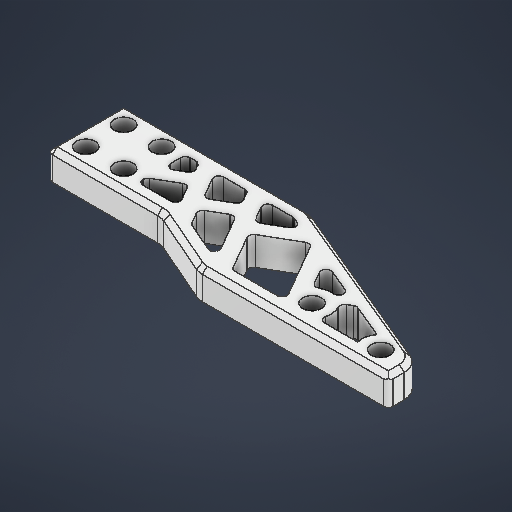
# Autodesk Inventor part: Tongs_l
Saved by Autodesk Inventor 2026.2 (Build 302298010, 298A)
## iProperties
Created: 2026-05-08
Part Number: Tongs_l
Material: ABS 플라스틱
Document SubType Name: Modeling
Designer: work
Density: 1.06 g/cm^3
Appearance: 매끄러움 - 흰색
Author: work
Autodesk Inventor part; units mm, degrees
ref_plane "YZ Plane" through (0, 0, 0) normal (1, 0, 0) x (0, 1, 0)
ref_plane "XZ Plane" through (0, 0, 0) normal (0, 1, 0) x (-1, 0, 0)
sketch "스케치1" plane through (0, 0, 0) normal (0, 1, 0) x (-1, 0, 0)
  line L0 (-4, 4) -> (4, 4) construction
  line L1 (4, 4) -> (4, -4) construction
  line L2 (4, -4) -> (-4, -4) construction
  line L3 (-4, -4) -> (-4, 4) construction
  line L4 (-4, 4) -> (4, -4) construction
  line L5 (4, 4) -> (-4, -4) construction
  circle A0 centre (4, 4) radius 2
  circle A1 centre (4, -4) radius 2
  circle A2 centre (-4, -4) radius 2
  circle A3 centre (-4, 4) radius 2
  line L6 (-8, 8) -> (8, 8)
  line L7 (8, 8) -> (8, -8)
  line L8 (8, -8) -> (-8, -8)
  line L9 (-8, -8) -> (-8, 8)
  line L10 (-8, 8) -> (8, -8) construction
  line L11 (8, 8) -> (-8, -8) construction
  line L12 (-8, 8) -> (-16, 8)
  line L13 (-16, 8) -> (-29.7477, 14)
  line L14 (-29.7477, 14) -> (-69.7477, 14)
  line L15 (-69.7477, 14) -> (-69.7477, 8)
  line L16 (-69.7477, 8) -> (-31.3982, -8)
  line L17 (-31.3982, -8) -> (-8, -8)
  line L18 (-8, -5) -> (-30.7974, -5)
  line L19 (-30.7974, -5) -> (-66.7477, 9.999)
  line L20 (-66.7477, 9.999) -> (-66.7477, 11)
  line L21 (-66.7477, 11) -> (-30.3739, 11)
  line L22 (-30.3739, 11) -> (-16.6261, 5)
  line L23 (-16.6261, 5) -> (-8, 5)
  line L24 (-48.5608, 11) -> (-42.0285, -0.3142)
  line L25 (-45.0967, 11) -> (-37.4652, -2.2181)
  line L26 (-30.3739, 11) -> (-21.1363, -5)
  line L27 (-33.838, 11) -> (-24.6004, -5)
  line L28 (-16.6261, 5) -> (-10.8526, -5)
  line L29 (-21.2571, 7.0211) -> (-14.3167, -5)
  line L30 (-37.4652, -2.2181) -> (-29.0212, 2.6571)
  line L31 (-27.5212, 0.059) -> (-33.9822, -3.6713)
  line L32 (-13.7394, 0) -> (-8, 3.3136)
  line L33 (-12.2394, -2.5981) -> (-8, -0.1505)
  line L34 (-17.7869, 1.0106) -> (-22.9016, -1.9424)
  line L35 (-24.4016, 0.6557) -> (-19.2869, 3.6086)
  line L36 (-46.0285, 6.614) -> (-51.3166, 3.5609)
  line L37 (-47.0285, 8.346) -> (-53.6386, 4.5297)
  point P0 (0, 0)
  point P1 (-30.7517, -1.8061)
  dimension "d0" = 8
  dimension "d1" = 8
  dimension "d2" = 4
  dimension "d3" = 4
  dimension "d4" = 4
  dimension "d5" = 4
  dimension "d6" = 4
  dimension "d7" = 8
  dimension "d8" = 15
  dimension "d9" = 40
  dimension "d10" = 6
  dimension "d11" = 38.3496
  dimension "d12" = 3
  dimension "d13" = 3
  dimension "d14" = 3
  dimension "d15" = 3
  dimension "d16" = 120
  dimension "d17" = 3
  dimension "d18" = 3
  dimension "d19" = 2
  dimension "d20" = 8
  dimension "d21" = 3
  constraints: 76 end point, 24 point on line, 19 parallel, 8 midpoint, 6 perpendicular, 4 centre point, 4 coincident, 3 horizontal, 5 other
  measures "d0" distance of L1.end L2.end
  measures "d1" distance of L0.end L1.end
  measures "d2" diameter of A0
  measures "d3" diameter of A1
  measures "d4" diameter of A2
  measures "d5" diameter of A3
  measures "d6" distance between parallel lines of L7 L1
  measures "d7" distance of L6.start L12.end
  measures "d8" distance of L12.end L13.end
  measures "d9" distance of L13.end L14.end
  measures "d10" distance of L14.end L15.end
  measures "d11" horizontal distance of L15.end L16.end
  measures "d12" distance between parallel lines of L13 L22
  measures "d13" distance between parallel lines of L24 L25
  measures "d14" distance between parallel lines of L27 L26
  measures "d15" distance between parallel lines of L29 L28
  measures "d16" angle of L21 L27
  measures "d17" distance between parallel lines of L34 L35
  measures "d18" distance from line of L30 point (-30.752, -1.806)
  measures "d19" distance between parallel lines of L37 L36
  measures "d20" distance from line of L24.end L36
  measures "d21" distance between parallel lines of L33 L32
extrude "돌출1" add sketch "스케치1" along normal blind 6 contours L6 L7 L8 L9 | L9 L23 L22 L21 L20 L19 L18 L17 L16 L15 L14 L13 L12 | L9 L33 L28 L32 | L28 L18 L29 L22 | L26 L18 L27 L21 | L29 L34 L26 L35 | L25 L19 L24 L21 | L27 L31 L19 L30 | L24 L36 L19 L37
sketch "스케치2" plane through (0, 6, 0) normal (0, 1, 0) x (1, 0, 0)
  line L0 (16, -8) -> (29.7477, -14) projected
  line L1 (29.7477, -14) -> (69.7477, -14) projected
  line L2 (69.7477, -14) -> (69.7477, -8) projected
  line L3 (69.7477, -8) -> (31.3982, 8) projected
  line L4 (31.3982, 8) -> (-8, 8) projected
  line L5 (-8, 8) -> (-8, -8) projected
  line L6 (-8, -8) -> (16, -8) projected
  line L7 (27.5212, -0.059) -> (24.6004, 5) projected
  line L8 (24.6004, 5) -> (30.7974, 5) projected
  line L9 (30.7974, 5) -> (33.9822, 3.6713) projected
  line L10 (33.9822, 3.6713) -> (27.5212, -0.059) projected
  line L11 (12.2394, 2.5981) -> (8, 0.1505) projected
  line L12 (8, 0.1505) -> (8, 5) projected
  line L13 (8, 5) -> (10.8526, 5) projected
  line L14 (10.8526, 5) -> (12.2394, 2.5981) projected
  line L15 (17.7869, -1.0106) -> (14.3167, 5) projected
  line L16 (14.3167, 5) -> (21.1363, 5) projected
  line L17 (21.1363, 5) -> (22.9016, 1.9424) projected
  line L18 (22.9016, 1.9424) -> (17.7869, -1.0106) projected
  line L19 (46.0285, -6.614) -> (42.0285, 0.3142) projected
  line L20 (42.0285, 0.3142) -> (51.3166, -3.5609) projected
  line L21 (51.3166, -3.5609) -> (46.0285, -6.614) projected
  line L22 (13.7394, 0) -> (16.6261, -5) projected
  line L23 (16.6261, -5) -> (8, -5) projected
  line L24 (8, -5) -> (8, -3.3136) projected
  line L25 (8, -3.3136) -> (13.7394, 0) projected
  line L26 (19.2869, -3.6086) -> (24.4016, -0.6557) projected
  line L27 (24.4016, -0.6557) -> (30.3739, -11) projected
  line L28 (30.3739, -11) -> (21.2571, -7.0211) projected
  line L29 (21.2571, -7.0211) -> (19.2869, -3.6086) projected
  line L30 (29.0212, -2.6571) -> (37.4652, 2.2181) projected
  line L31 (37.4652, 2.2181) -> (45.0967, -11) projected
  line L32 (45.0967, -11) -> (33.838, -11) projected
  line L33 (33.838, -11) -> (29.0212, -2.6571) projected
  circle A0 centre (4, -4) radius 2 projected
  circle A1 centre (4, 4) radius 2 projected
  circle A2 centre (-4, 4) radius 2 projected
  circle A3 centre (-4, -4) radius 2 projected
  line L34 (47.0285, -8.346) -> (53.6386, -4.5297) projected
  line L35 (53.6386, -4.5297) -> (66.7477, -9.999) projected
  line L36 (66.7477, -9.999) -> (66.7477, -11) projected
  line L37 (66.7477, -11) -> (48.5608, -11) projected
  line L38 (48.5608, -11) -> (47.0285, -8.346) projected
  point P0 (0, 0)
  constraints: 4 coincident
hole "구멍1" at (-4, 6, 4) at (4, 6, 4) at (4, 6, -4) at (-4, 6, -4) direction (0, -1, 0) diameter 4 end through all counterbore diameter 6.2 counterbore depth 3
fillet "모깎기1" radius 1 30 edges at (8, 3, -5) (8, 3, -0.1505) (10.8526, 3, -5) (12.2394, 3, -2.5981) (13.7394, 3, 0) (8, 3, 3.3136) (8, 3, 5) (16.6261, 3, 5) (17.7869, 3, 1.0106) (33.9822, 3, -3.6713) (30.7974, 3, -5) (27.5212, 3, 0.059) (24.6004, 3, -5) (22.9016, 3, -1.9424) (21.1363, 3, -5) (42.0285, 3, -0.3142) (46.0285, 3, 6.614) (53.6386, 3, 4.5297) (66.7477, 3, 9.999) (51.3166, 3, 3.5609) (24.4016, 3, 0.6557) (30.3739, 3, 11) (21.2571, 3, 7.0211) (45.0967, 3, 11) (37.4652, 3, -2.2181) (33.838, 3, 11) (29.0212, 3, 2.6571) (48.5608, 3, 11) (66.7477, 3, 11) (47.0285, 3, 8.346)
fillet "모깎기2" radius 4 4 edges at (16, 3, 8) (29.7477, 3, 14) (69.7477, 3, 8) (31.3982, 3, -8)
fillet "모깎기3" radius 1 3 edges at (-8, 3, 8) (-8, 3, -8) (69.7477, 3, 14)
chamfer "모따기1" distance 1 angle 45 14 edges at (29.7653, 0, 13.9156) (49.6652, 0, 14) (69.4548, 0, 13.7071) (69.7477, 0, 11.8327) (69.0764, 0, 8.4473) (49.7126, 0, -0.3589) (31.3826, 0, -7.9221) (11.7986, 0, -8) (-7.7071, 0, -7.7071) (-8, 0, 0) (-7.7071, 0, 7.7071) (4.0826, 0, 8) (15.9824, 0, 8.0844) (22.8739, 0, 11)
ref_plane "작업 평면1" through (0, 0, 0) normal (0, -1, 0) x (1, 0, 0)
mirror "미러1" about plane through (0, 0, 0) normal (0, -1, 0) of "돌출1", "구멍1"
sketch "스케치3" plane through (-8, 0, 8) normal (0, 0, 1) x (1, 0, 0)
  line L0 (39.3982, 0) -> (0, 0) projected
  line L1 (0, 0) -> (80.7132, 0)
  line L2 (80.7132, 0) -> (80.7132, 23.1033)
  line L3 (80.7132, 23.1033) -> (0, 23.1033)
  line L4 (0, 23.1033) -> (0, 0)
  point P0 (8, 0)
  constraints: 8 end point, 2 parallel, 1 horizontal, 1 perpendicular
extrude "돌출2" cut sketch "스케치3" along normal through all both and the other way through all
fillet "모깎기4" radius 1 34 edges at (66.7477, -3, 9.999) (53.6386, -3, 4.5297) (66.7477, -3, 11) (37.4652, -3, -2.2181) (46.0285, -3, 6.614) (19.2869, -3, 3.6086) (22.9016, -3, -1.9424) (30.7974, -3, -5) (29.0212, -3, 2.6571) (8, -3, -0.1505) (8, -3, 3.3136) (51.3166, -3, 3.5609) (47.0285, -3, 8.346) (48.5608, -3, 11) (45.0967, -3, 11) (33.838, -3, 11) (30.3739, -3, 11) (21.2571, -3, 7.0211) (42.0285, -3, -0.3142) (33.9822, -3, -3.6713) (24.4016, -3, 0.6557) (21.1363, -3, -5) (24.6004, -3, -5) (27.5212, -3, 0.059) (17.7869, -3, 1.0106) (14.3167, -3, -5) (8, -3, 5) (16.6261, -3, 5) (13.7394, -3, 0) (12.2394, -3, -2.5981) (10.8526, -3, -5) (8, -3, -5) (-8, -3, -8) (-8, -3, 8)
fillet "모깎기5" radius 4 4 edges at (29.7477, -3, 14) (31.3982, -3, -8) (16, -3, 8) (69.7477, -3, 8)
chamfer "모따기2" distance 1 angle 45 12 edges at (49.7126, 0, -0.3589) (31.3826, 0, -7.9221) (11.7986, 0, -8) (-7.7071, 0, -7.7071) (-8, 0, 0) (-7.7071, 0, 7.7071) (4.0826, 0, 8) (15.9824, 0, 8.0844) (22.8739, 0, 11) (29.7653, 0, 13.9156) (50.1652, 0, 14) (69.7477, 0, 12.3327)
sketch "스케치4" plane through (-8, -6, -7) normal (0, -1, 0) x (1, 0, 0)
  arc A0 (38.5972, -1) -> (40.1374, -0.6916) centre (38.5972, 3) ccw projected
  line L0 (75.2879, 13.9737) -> (40.1374, -0.6916) projected
  line L1 (77.7477, 21) -> (77.7477, 17.6653) projected
  line L2 (38.5826, 21) -> (77.7477, 21) projected
  arc A1 (38.5826, 21) -> (36.9826, 20.6661) centre (38.5826, 17) ccw projected
  line L3 (24.7652, 15.3339) -> (36.9826, 20.6661) projected
  arc A2 (23.1652, 15) -> (24.7652, 15.3339) centre (23.1652, 19) ccw projected
  line L4 (1, 15) -> (23.1652, 15) projected
  arc A3 (1, 15) -> (0, 14) centre (1, 14) ccw projected
  line L5 (0, 0) -> (0, 14) projected
  arc A4 (0, 0) -> (1, -1) centre (1, 0) ccw projected
  line L6 (38.5972, -1) -> (1, -1) projected
  circle A5 centre (4, 3) radius 3.1 projected
  circle A6 centre (4, 11) radius 3.1 projected
  circle A7 centre (12, 11) radius 3.1 projected
  circle A8 centre (12, 3) radius 3.1 projected
  line L7 (40.2317, 4.3394) -> (36.3872, 6.559) projected
  arc A9 (40.1168, 2.5504) -> (40.2317, 4.3394) centre (39.7317, 3.4733) ccw projected
  line L8 (38.9822, 2.0771) -> (40.1168, 2.5504) projected
  arc A10 (38.5972, 2) -> (38.9822, 2.0771) centre (38.5972, 3) ccw projected
  line L9 (34.3324, 2) -> (38.5972, 2) projected
  arc A11 (33.4664, 3.5) -> (34.3324, 2) centre (34.3324, 3) ccw projected
  line L10 (35.0212, 6.193) -> (33.4664, 3.5) projected
  arc A12 (36.3872, 6.559) -> (35.0212, 6.193) centre (35.8872, 5.693) ccw projected
  line L11 (16, 5.1175) -> (16, 3) projected
  arc A13 (17.5, 5.9835) -> (16, 5.1175) centre (17, 5.1175) ccw projected
  line L12 (19.3734, 4.9019) -> (17.5, 5.9835) projected
  arc A14 (19.7394, 3.5359) -> (19.3734, 4.9019) centre (18.8734, 4.0359) ccw projected
  line L13 (19.1413, 2.5) -> (19.7394, 3.5359) projected
  arc A15 (18.2753, 2) -> (19.1413, 2.5) centre (18.2753, 3) ccw projected
  line L14 (17, 2) -> (18.2753, 2) projected
  arc A16 (16, 3) -> (17, 2) centre (17, 3) ccw projected
  line L15 (30.0356, 5.5576) -> (26.653, 7.5106) projected
  arc A17 (30.4016, 4.1916) -> (30.0356, 5.5576) centre (29.5356, 4.6916) ccw projected
  line L16 (29.4249, 2.5) -> (30.4016, 4.1916) projected
  arc A18 (28.5589, 2) -> (29.4249, 2.5) centre (28.5589, 3) ccw projected
  line L17 (24.0488, 2) -> (28.5589, 2) projected
  arc A19 (23.1828, 3.5) -> (24.0488, 2) centre (24.0488, 3) ccw projected
  line L18 (25.2869, 7.1445) -> (23.1828, 3.5) projected
  arc A20 (26.653, 7.5106) -> (25.2869, 7.1445) centre (26.153, 6.6445) ccw projected
  arc A21 (54.8946, 13.114) -> (53.5285, 12.748) centre (54.3946, 12.248) ccw projected
  line L19 (57.5661, 11.5715) -> (54.8946, 13.114) projected
  arc A22 (57.4512, 9.7826) -> (57.5661, 11.5715) centre (57.0661, 10.7055) ccw projected
  line L20 (52.7588, 7.8249) -> (57.4512, 9.7826) projected
  arc A23 (51.5077, 9.2478) -> (52.7588, 7.8249) centre (52.3737, 8.7478) ccw projected
  line L21 (53.5285, 12.748) -> (51.5077, 9.2478) projected
  line L22 (16.5, 10.025) -> (20.8734, 7.5) projected
  arc A24 (16, 10.891) -> (16.5, 10.025) centre (17, 10.891) ccw projected
  line L23 (16, 11) -> (16, 10.891) projected
  arc A25 (17, 12) -> (16, 11) centre (17, 11) ccw projected
  line L24 (22.8941, 12) -> (17, 12) projected
  arc A26 (23.7601, 10.5) -> (22.8941, 12) centre (22.8941, 11) ccw projected
  line L25 (22.2394, 7.866) -> (23.7601, 10.5) projected
  arc A27 (20.8734, 7.5) -> (22.2394, 7.866) centre (21.3734, 8.366) ccw projected
  arc A28 (27.7869, 11.4747) -> (28.153, 10.1086) centre (28.653, 10.9747) ccw projected
  line L26 (29.0926, 13.7362) -> (27.7869, 11.4747) projected
  arc A29 (29.5587, 14.1527) -> (29.0926, 13.7362) centre (29.9587, 13.2362) ccw projected
  line L27 (35.5881, 16.7842) -> (29.5587, 14.1527) projected
  arc A30 (36.8541, 15.3677) -> (35.5881, 16.7842) centre (35.9881, 15.8677) ccw projected
  line L28 (32.9016, 8.5217) -> (36.8541, 15.3677) projected
  arc A31 (31.5356, 8.1557) -> (32.9016, 8.5217) centre (32.0356, 9.0217) ccw projected
  line L29 (28.153, 10.1086) -> (31.5356, 8.1557) projected
  line L30 (51.3646, 18) -> (42.4153, 18) projected
  arc A32 (52.2307, 16.5) -> (51.3646, 18) centre (51.3646, 17) ccw projected
  line L31 (45.9652, 5.6479) -> (52.2307, 16.5) projected
  arc A33 (44.5992, 5.2819) -> (45.9652, 5.6479) centre (45.0992, 6.1479) ccw projected
  line L32 (37.8872, 9.1571) -> (44.5992, 5.2819) projected
  arc A34 (37.5212, 10.5231) -> (37.8872, 9.1571) centre (38.3872, 10.0231) ccw projected
  line L33 (41.5493, 17.5) -> (37.5212, 10.5231) projected
  arc A35 (42.4153, 18) -> (41.5493, 17.5) centre (42.4153, 17) ccw projected
  line L34 (72.1531, 18) -> (57.1381, 18) projected
  arc A36 (72.5381, 16.0771) -> (72.1531, 18) centre (72.1531, 17) ccw projected
  line L35 (62.0952, 11.7202) -> (72.5381, 16.0771) projected
  arc A37 (61.2102, 11.7771) -> (62.0952, 11.7202) centre (61.7102, 12.6431) ccw projected
  line L36 (55.8946, 14.846) -> (61.2102, 11.7771) projected
  arc A38 (55.5285, 16.2121) -> (55.8946, 14.846) centre (56.3946, 15.7121) ccw projected
  line L37 (56.2721, 17.5) -> (55.5285, 16.2121) projected
  arc A39 (57.1381, 18) -> (56.2721, 17.5) centre (57.1381, 17) ccw projected
  circle A40 centre (56.3946, 15.7121) radius 2
  circle A41 centre (56.3946, 15.7121) radius 4
  circle A42 centre (72.1531, 17) radius 4
  circle A43 centre (72.1531, 17) radius 2
  arc A44 (75.2879, 13.9737) -> (77.7477, 17.6653) centre (73.7477, 17.6653) ccw projected
  point P0 (8, 7)
  point P1 (53.5978, 12.8523)
  point P2 (57.1858, 11.7911)
  point P3 (59.2487, 12.9095)
  point P4 (59.6756, 18)
  point P5 (56.4356, 17.7116)
  point P6 (57.3946, 13.98)
  point P7 (70.9396, 15.4102)
  point P8 (70.421, 18)
  point P9 (68.2801, 18)
  point P10 (68.9637, 14.5858)
  dimension "d45" = 4
  dimension "d46" = 8
  dimension "d47" = 8
  dimension "d48" = 4
  constraints: 4 centre point, 4 coincident
  measures "d45" diameter of A40
  measures "d46" diameter of A41
  measures "d47" diameter of A42
  measures "d48" diameter of A43
extrude "돌출3" add sketch "스케치4" against normal up to surface (6 mm away) contours A42 L34 A43 L35 | A41 L36 A40 A39 L34 | A21 L19 A41 picked at (68.9761, 16.0603)
extrude "돌출4" cut sketch "스케치4" against normal through all contours L35 A36 L34 A43 | A40 A39 L37 A38 L36 picked at (71.6143, 15.5497) picked at (55.7626, 17.0688)
fillet "모깎기6" radius 1 4 edges at (51.6756, -3, 11) (51.2487, -3, 5.9095) (45.5978, -3, 5.8523) (49.1858, -3, 4.7911)
sketch "스케치5" plane through (-8, -6, -7) normal (0, -1, 0) x (1, 0, 0)
  circle A0 centre (56.3946, 15.7121) radius 2 projected
  circle A1 centre (72.1531, 17) radius 2 projected
  point P0 (8, 7)
  point P1 (68.5494, 19.239)
  constraints: 2 coincident
hole "구멍2" at (48.3946, -6, 8.7121) at (64.1531, -6, 10) direction (0, 1, 0) diameter 4 end through all counterbore diameter 6.2 counterbore depth 3
fillet "모깎기7" radius 1 1 edges at (69.7477, -3.5, 14)
